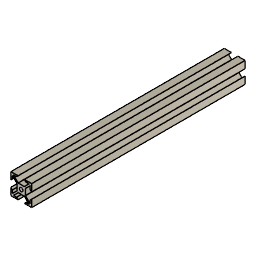
wid_alluminium_v4 (Autodesk Fusion 360 design; units mm, degrees)
part number: 2026-11-03-22-11-59-727
Autodesk Fusion 360 part; units mm, degrees
sketch "Sketch3" plane through (0, 0, 0) normal (0, 1, 0) x (1, 0, 0)
  line L0 (-3, -3) -> (-3, -10)
  line L1 (10, -3) -> (3, -10)
  line L2 (-8.5, 4.5) -> (-8.5, 8.5)
  line L3 (-4, -4) -> (4, -4)
  line L4 (-4.5, -8.5) -> (-8.5, -8.5)
  line L5 (10, 10) -> (-10, 10)
  line L6 (-3, 3) -> (-10, 3)
  line L7 (-10, 3) -> (-3, 10)
  line L8 (10, -3) -> (10, -10)
  line L9 (-8.5, -4.5) -> (-4.5, -4.5)
  line L10 (0, 2.5) -> (0, 20)
  line L11 (-10, 10) -> (-10, -10)
  line L12 (-3, 10) -> (-3, 3)
  line L13 (-8.5, -8.5) -> (-8.5, -4.5)
  line L14 (-8.5, 8.5) -> (-4.5, 8.5)
  line L15 (10, 10) -> (-10, -10) construction
  line L16 (-4, 4) -> (4, -4) construction
  line L17 (4.5, 8.5) -> (8.5, 8.5)
  line L18 (8.5, -8.5) -> (4.5, -8.5)
  line L19 (-10, -10) -> (10, -10)
  line L20 (3, -10) -> (3, -3)
  line L21 (4, 4) -> (-4, -4) construction
  line L22 (-10, -3) -> (-3, -3)
  line L23 (10.5303, 9.4697) -> (-9.4697, -10.5303)
  line L24 (8.5, -4.5) -> (8.5, -8.5)
  line L25 (-4.5, -4.5) -> (-4.5, -8.5)
  line L26 (1.75, 0) -> (22.5, 0)
  line L27 (-4, 4) -> (-4, -4)
  line L28 (-4.5, 4.5) -> (-8.5, 4.5)
  line L29 (8.5, 4.5) -> (4.5, 4.5)
  line L30 (4, 4) -> (-4, 4)
  line L31 (-10, -3) -> (-3, -10)
  line L32 (10, 3) -> (3, 3)
  circle A0 centre (0, 0) radius 1.75
  line L33 (3, -3) -> (10, -3)
  line L34 (10, -10) -> (3, -10)
  line L35 (4.5, -4.5) -> (8.5, -4.5)
  line L36 (4.5, -8.5) -> (4.5, -4.5)
  line L37 (0, 0) -> (10, -10)
  line L38 (4, -4) -> (4, 4)
  line L39 (-4.5, 8.5) -> (-4.5, 4.5)
  line L40 (-10.5303, 9.4697) -> (9.4697, -10.5303)
  line L41 (3, 3) -> (3, 10)
  line L42 (-10, 10) -> (10, -10) construction
  line L43 (10, 3) -> (3, 10)
  line L44 (-9.4697, 10.5303) -> (10.5303, -9.4697)
  line L45 (8.5, 8.5) -> (8.5, 4.5)
  line L46 (9.4697, 10.5303) -> (-10.5303, -9.4697)
  line L47 (4.5, 4.5) -> (4.5, 8.5)
  line L48 (10, -10) -> (10, 10)
  dimension "d23" = 1.5
  dimension "d24" = 0.75
  dimension "d25" = -1.5
  dimension "d27" = 360
  dimension "d28" = 20
  dimension "d29" = 20
  dimension "d30" = 10
  dimension "d31" = 10
  dimension "d32" = 8
  dimension "d33" = 8
  dimension "d34" = 7
  dimension "d35" = 7
  dimension "d36" = 3.5
  constraint horizontal L30
  constraint perpendicular L27 L30
  constraint parallel L3 L30
  constraint parallel L27 L38
  constraint coincident A0.centre L21
  constraint coincident A0.centre L16
  constraint coincident A0.centre L37.start
  constraint horizontal L34
  constraint vertical L20
  constraint horizontal L33
  constraint vertical L8
  constraint parallel L37 L42
  constraint symmetric L23.start L40.start L10
  constraint symmetric L23.end L40.end L10
  constraint symmetric L46.start L44.start L10
  constraint symmetric L44.end L46.end L10
  constraint symmetric L22.start L1.start L10
  constraint symmetric L0.end L1.end L10
  constraint symmetric L22.start L6.end L26
  constraint symmetric L0.end L7.end L26
  constraint symmetric L1.start L32.start L26
  constraint symmetric L1.end L41.end L26
  measures "d28" distance of L8.end L11.end
  measures "d29" distance of L5.end L11.end
  measures "d30" distance of A0.centre L5
  measures "d31" distance of A0.centre L48
  measures "d32" distance of L3.start L3.end
  measures "d33" distance of L16.start L3.start
  measures "d34" distance of L8.end L1.end
  measures "d35" distance of L8.end L1.start
  measures "d36" diameter of A0
extrude "Extrude3" add sketch "Sketch3" along normal mid plane 205 contours L0 L3 L22 L23 L27 A0 L46 | L0 L3 L22 L27 | L0 L3 L9 L22 L23 L25 L27 L46 | L3 L23 A0 L40 | L27 A0 L40 L46 | L4 L19 L23 L31 | L9 L23 L25 L31 L46 | L3 L20 A0 L37 L40 | L11 L13 L31 L46 | L6 L12 L27 L30 A0 L40 L44 | L1 L18 L19 L34 L40 | L4 L11 L13 L19 L23 L46 | L4 L13 L23 L31 L46 | L3 L20 L37 | L3 L20 L36 L37 L40 | L2 L7 L11 L40 | L6 L12 L27 L30 | L6 L12 L27 L28 L30 L39 L40 L44 | L18 L19 L34 L37 L40 | L33 L35 L37 L38 L44 | L33 L37 L38 | A0 L33 L37 L38 L44 | L1 L36 L37 L40 | L2 L5 L11 L14 L40 L44 | L7 L28 L39 L40 L44 | L30 A0 L44 L46 | L1 L18 L37 L40 | L8 L24 L37 L44 L48 | L1 L35 L37 L44 | L26 A0 L38 L44 | L2 L7 L14 L40 L44 | L23 L30 L32 A0 L38 L41 L46 | L1 L24 L37 L44 | L1 L8 L24 L44 L48 | L23 L26 A0 L38 | L5 L7 L14 L44 | L23 L29 L30 L32 L38 L41 L46 L47 | L30 L32 L38 L41 | L5 L17 L43 L46 | L23 L29 L43 L46 L47 | L23 L43 L45 L48 | L5 L17 L23 L45 L46 L48 | L17 L23 L43 L45 L46
equation "d37 = ( 205 / 2 ) * 1 mm"
